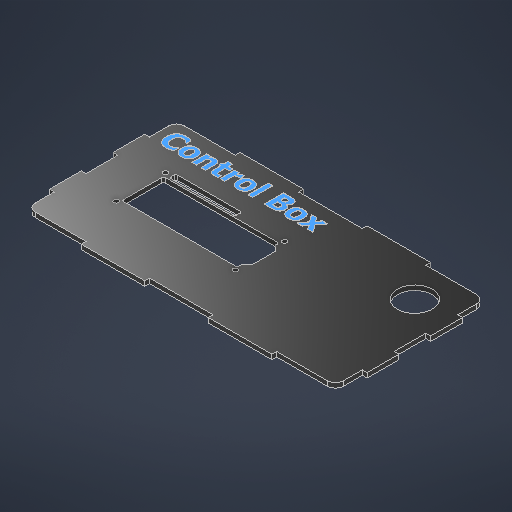
# Autodesk Inventor part: ControlBoxCeiling
Saved by Autodesk Inventor 2027.1 (Build 311270010, 270A)
## iProperties
Created: 2026-10-13
Part Number: ControlBoxCeiling
Material: MDF Medium Density Fiberboard
Document SubType Name: Modeling
Designer: SDS Scholar
Density: 0.8 g/cm^3
Appearance: Glossy - Black
Mass: 41.8002 g
Surface Area: 376.272 cm^2
Volume: 52.2502 cm^3
Author: SDS Scholar
Autodesk Inventor part; units mm, degrees
ref_plane "YZ Plane" through (0, 0, 0) normal (1, 0, 0) x (0, 1, 0)
ref_plane "XZ Plane" through (0, 0, 0) normal (0, 1, 0) x (-1, 0, 0)
ref_plane "XY Plane" through (0, 0, 0) normal (0, 0, 1) x (1, 0, 0)
sketch "Sketch1" plane through (0, 0, 0) normal (0, 1, 0) x (-1, 0, 0)
  line L0 (100, 50) -> (-100, 50)
  line L1 (-100, 50) -> (-100, -50)
  line L2 (-100, -50) -> (100, -50)
  line L3 (100, -50) -> (100, 50)
  line L4 (0, -50) -> (0, 81.8372) construction
  line L5 (0, 0) -> (100, 0) construction
  circle A0 centre (-75, -25) radius 11
  dimension "d0" = 100
  dimension "d1" = 200
  dimension "d21" = 22
  dimension "d22" = 25
  dimension "d23" = 25
  constraints: 12 end point, 2 midpoint, 2 parallel, 2 perpendicular, 1 centre point, 1 horizontal, 1 horizontal alignment, 1 vertical, 1 vertical alignment
  measures "d0" distance of L2.end L0.start
  measures "d1" distance of L1.end L2.end
  measures "d21" diameter of A0
  measures "d22" distance from line of L2 A0.centre
  measures "d23" distance from line of L1 A0.centre
extrude "Extrusion1" add sketch "Sketch1" along normal blind 3
sketch "Sketch2" plane through (0, 3, 0) normal (0, 1, 0) x (1, 0, 0)
  line L0 (100, -50) -> (100, 50) projected
  line L1 (100, 50) -> (-100, 50) projected
  line L2 (-100, 50) -> (-100, -50) projected
  line L3 (-100, -50) -> (100, -50) projected
  circle A0 centre (75, 25) radius 11 projected
  line L4 (-97, 47) -> (97, 47)
  line L5 (97, 47) -> (97, -47)
  line L6 (97, -47) -> (-97, -47)
  line L7 (-97, -47) -> (-97, 47)
  line L8 (-100, 50) -> (-60, 50)
  line L9 (-60, 50) -> (-60, 47)
  line L10 (-60, 47) -> (-100, 47)
  line L11 (-100, 47) -> (-100, 50)
  line L12 (-100, 0) -> (100, 0) construction
  line L13 (0, 50) -> (0, -50) construction
  line L14 (-20, 50) -> (-20, 47)
  line L15 (20, 50) -> (20, 47)
  line L16 (60, 50) -> (60, 47)
  line L17 (-60, -50) -> (-60, -47)
  line L18 (-20, -50) -> (-20, -47)
  line L19 (20, -50) -> (20, -47)
  line L20 (60, -50) -> (60, -47)
  line L21 (-100, 50) -> (-100, -50) projected
  line L22 (-100, 50) -> (-97, 50)
  line L23 (-97, 50) -> (-97, 30)
  line L24 (-97, 30) -> (-100, 30)
  line L25 (-100, 30) -> (-100, 50)
  line L26 (-97, 10) -> (-100, 10)
  line L27 (-97, -10) -> (-100, -10)
  line L28 (-97, -30) -> (-100, -30)
  line L29 (97, 30) -> (100, 30)
  line L30 (97, 10) -> (100, 10)
  line L31 (97, -10) -> (100, -10)
  line L32 (97, -30) -> (100, -30)
  dimension "d64" = 3
  dimension "d65" = 40
  dimension "d68" = 40
  dimension "d73" = 20
  dimension "d76" = 20
  constraints: 56 end point, 16 symmetric about line, 4 midpoint, 4 parallel, 3 horizontal, 2 perpendicular, 2 point on line, 1 vertical, 21 other
  measures "d64" distance between parallel lines of L1 L4
  measures "d65" distance of L9.end L10.end
  measures "d68" distance of L8.end L14.start
  measures "d73" distance of L22.end L23.end
  measures "d76" distance of L23.end L26.start
extrude "Extrusion2" cut sketch "Sketch2" against normal through all contours L3 L20 L6 L5 L32 L0 | L31 L5 L30 L0 | L3 L18 L6 L19 | L29 L5 L4 L16 L1 L0 | L3 L2 L28 L7 L6 L17 | L15 L4 L14 L1 | L2 L26 L7 L27 | L9 L4 L23 L1 | L2 L10 L7 L24 | L23 L10 L2 L1
sketch "Sketch3" plane through (0, 3, 0) normal (0, 1, 0) x (1, 0, 0)
  line L0 (-92.3688, 42.1211) -> (16.5966, 42.1211) construction
  line L1 (16.5966, 42.1211) -> (16.5966, 25.6389) construction
  line L2 (16.5966, 25.6389) -> (-92.3688, 25.6389) construction
  line L3 (-92.3688, 25.6389) -> (-92.3688, 42.1211) construction
  spline S0 degree 2 poles (-85.8437, 29.1401) (-88.5921, 29.1401) (-91.8152, 32.4619) (-91.8152, 35.4674) knots 0 0 0 1 2 2 2
  spline S1 degree 2 poles (-91.8152, 35.4674) (-91.8152, 38.3642) (-88.5823, 41.8146) (-85.8338, 41.8146) knots 0 0 0 1 2 2 2
  spline S2 degree 2 poles (-85.8338, 41.8146) (-85.1121, 41.8146) (-83.9455, 41.6465) (-83.4116, 41.5081) knots 0 0 0 1 2 2 2
  spline S3 degree 2 poles (-83.4116, 41.5081) (-82.9964, 41.3796) (-82.0176, 40.9545) (-81.7111, 40.7963) knots 0 0 0 1 2 2 2
  line L4 (-81.7111, 40.7963) -> (-81.7111, 37.8896)
  line L5 (-81.7111, 37.8896) -> (-82.0176, 37.8896)
  spline S4 degree 2 poles (-82.0176, 37.8896) (-82.245, 38.0874) (-82.9173, 38.641) (-83.3424, 38.8981) knots 0 0 0 1 2 2 2
  spline S5 degree 2 poles (-83.3424, 38.8981) (-83.7675, 39.165) (-84.7858, 39.5308) (-85.3494, 39.5308) knots 0 0 0 1 2 2 2
  spline S6 degree 2 poles (-85.3494, 39.5308) (-86.0118, 39.5308) (-87.1092, 39.1156) (-87.6134, 38.5916) knots 0 0 0 1 2 2 2
  spline S7 degree 2 poles (-87.6134, 38.5916) (-88.0682, 38.1269) (-88.6515, 36.5352) (-88.6515, 35.4576) knots 0 0 0 1 2 2 2
  spline S8 degree 2 poles (-88.6515, 35.4576) (-88.6515, 34.3206) (-88.0484, 32.7684) (-87.5541, 32.2939) knots 0 0 0 1 2 2 2
  spline S9 degree 2 poles (-87.5541, 32.2939) (-87.0795, 31.8292) (-85.9129, 31.4238) (-85.3296, 31.4238) knots 0 0 0 1 2 2 2
  spline S10 degree 2 poles (-85.3296, 31.4238) (-84.7265, 31.4238) (-83.6291, 31.8292) (-83.2534, 32.0764) knots 0 0 0 1 2 2 2
  spline S11 degree 2 poles (-83.2534, 32.0764) (-82.8382, 32.3235) (-82.2153, 32.8475) (-81.9879, 33.0551) knots 0 0 0 1 2 2 2
  line L6 (-81.9879, 33.0551) -> (-81.7111, 33.0551)
  line L7 (-81.7111, 33.0551) -> (-81.7111, 30.188)
  spline S12 degree 2 poles (-81.7111, 30.188) (-82.0473, 30.0298) (-82.9272, 29.6344) (-83.4017, 29.496) knots 0 0 0 1 2 2 2
  spline S13 degree 2 poles (-83.4017, 29.496) (-83.9751, 29.318) (-84.9737, 29.1401) (-85.8437, 29.1401) knots 0 0 0 1 2 2 2
  spline S14 degree 2 poles (-71.2413, 33.9746) (-71.2413, 31.7007) (-73.7228, 29.0906) (-75.9868, 29.0906) knots 0 0 0 1 2 2 2
  spline S15 degree 2 poles (-75.9868, 29.0906) (-78.2409, 29.0906) (-80.7422, 31.7007) (-80.7422, 33.9746) knots 0 0 0 1 2 2 2
  spline S16 degree 2 poles (-80.7422, 33.9746) (-80.7422, 36.2683) (-78.2409, 38.8684) (-75.9868, 38.8684) knots 0 0 0 1 2 2 2
  spline S17 degree 2 poles (-75.9868, 38.8684) (-73.7327, 38.8684) (-71.2413, 36.2584) (-71.2413, 33.9746) knots 0 0 0 1 2 2 2
  spline S18 degree 2 poles (-74.1776, 33.9548) (-74.1776, 34.7754) (-74.4445, 35.8728) (-74.6818, 36.199) knots 0 0 0 1 2 2 2
  spline S19 degree 2 poles (-74.6818, 36.199) (-74.9388, 36.5451) (-75.5815, 36.812) (-75.9868, 36.812) knots 0 0 0 1 2 2 2
  spline S20 degree 2 poles (-75.9868, 36.812) (-76.3823, 36.812) (-77.0051, 36.5747) (-77.2622, 36.2386) knots 0 0 0 1 2 2 2
  spline S21 degree 2 poles (-77.2622, 36.2386) (-77.5093, 35.9222) (-77.8059, 34.805) (-77.8059, 33.9548) knots 0 0 0 1 2 2 2
  spline S22 degree 2 poles (-77.8059, 33.9548) (-77.8059, 33.1144) (-77.5291, 32.0764) (-77.3017, 31.76) knots 0 0 0 1 2 2 2
  spline S23 degree 2 poles (-77.3017, 31.76) (-77.0743, 31.4436) (-76.3823, 31.147) (-75.967, 31.147) knots 0 0 0 1 2 2 2
  spline S24 degree 2 poles (-75.967, 31.147) (-75.621, 31.147) (-74.9092, 31.4436) (-74.6917, 31.7402) knots 0 0 0 1 2 2 2
  spline S25 degree 2 poles (-74.6917, 31.7402) (-74.4445, 32.0862) (-74.1776, 33.0848) (-74.1776, 33.9548) knots 0 0 0 1 2 2 2
  line L8 (-61.1075, 29.3773) -> (-63.9944, 29.3773)
  line L9 (-63.9944, 29.3773) -> (-63.9944, 33.935)
  spline S26 degree 2 poles (-63.9944, 33.935) (-63.9944, 34.4986) (-64.0834, 35.6059) (-64.202, 35.8629) knots 0 0 0 1 2 2 2
  spline S27 degree 2 poles (-64.202, 35.8629) (-64.3503, 36.1793) (-64.904, 36.4462) (-65.3785, 36.4462) knots 0 0 0 1 2 2 2
  spline S28 degree 2 poles (-65.3785, 36.4462) (-65.7246, 36.4462) (-66.4463, 36.1793) (-66.8516, 35.8926) knots 0 0 0 1 2 2 2
  line L10 (-66.8516, 35.8926) -> (-66.8516, 29.3773)
  line L11 (-66.8516, 29.3773) -> (-69.7187, 29.3773)
  line L12 (-69.7187, 29.3773) -> (-69.7187, 38.5817)
  line L13 (-69.7187, 38.5817) -> (-66.8516, 38.5817)
  line L14 (-66.8516, 38.5817) -> (-66.8516, 37.5634)
  spline S29 degree 2 poles (-66.8516, 37.5634) (-66.1497, 38.1566) (-64.815, 38.8289) (-64.0043, 38.8289) knots 0 0 0 1 2 2 2
  spline S30 degree 2 poles (-64.0043, 38.8289) (-62.6004, 38.8289) (-61.1075, 37.0493) (-61.1075, 35.3686) knots 0 0 0 1 2 2 2
  line L15 (-61.1075, 35.3686) -> (-61.1075, 29.3773)
  spline S31 degree 2 poles (-55.4623, 29.1994) (-57.2122, 29.1994) (-58.8139, 30.6428) (-58.8139, 32.284) knots 0 0 0 1 2 2 2
  line L16 (-58.8139, 32.284) -> (-58.8139, 36.5846)
  line L17 (-58.8139, 36.5846) -> (-59.9113, 36.5846)
  line L18 (-59.9113, 36.5846) -> (-59.9113, 38.5817)
  line L19 (-59.9113, 38.5817) -> (-58.8139, 38.5817)
  line L20 (-58.8139, 38.5817) -> (-58.8139, 41.2115)
  line L21 (-58.8139, 41.2115) -> (-55.9468, 41.2115)
  line L22 (-55.9468, 41.2115) -> (-55.9468, 38.5817)
  line L23 (-55.9468, 38.5817) -> (-53.1785, 38.5817)
  line L24 (-53.1785, 38.5817) -> (-53.1785, 36.5846)
  line L25 (-53.1785, 36.5846) -> (-55.9468, 36.5846)
  line L26 (-55.9468, 36.5846) -> (-55.9468, 33.3122)
  spline S32 degree 2 poles (-55.9468, 33.3122) (-55.9468, 32.8277) (-55.927, 32.106) (-55.8084, 31.8193) knots 0 0 0 1 2 2 2
  spline S33 degree 2 poles (-55.8084, 31.8193) (-55.6897, 31.5326) (-55.1064, 31.1965) (-54.5528, 31.1965) knots 0 0 0 1 2 2 2
  spline S34 degree 2 poles (-54.5528, 31.1965) (-54.3155, 31.1965) (-53.574, 31.3942) (-53.4257, 31.4733) knots 0 0 0 1 2 2 2
  line L27 (-53.4257, 31.4733) -> (-53.1785, 31.4733)
  line L28 (-53.1785, 31.4733) -> (-53.1785, 29.4564)
  spline S35 degree 2 poles (-53.1785, 29.4564) (-53.6432, 29.3378) (-54.6912, 29.1994) (-55.4623, 29.1994) knots 0 0 0 1 2 2 2
  line L29 (-45.8328, 35.8629) -> (-46.0701, 35.8629)
  spline S36 degree 2 poles (-46.0701, 35.8629) (-46.2382, 35.9222) (-46.861, 35.9815) (-47.2367, 35.9815) knots 0 0 0 1 2 2 2
  spline S37 degree 2 poles (-47.2367, 35.9815) (-47.6816, 35.9815) (-48.6802, 35.7146) (-49.1448, 35.5367) knots 0 0 0 1 2 2 2
  line L30 (-49.1448, 35.5367) -> (-49.1448, 29.3773)
  line L31 (-49.1448, 29.3773) -> (-52.0119, 29.3773)
  line L32 (-52.0119, 29.3773) -> (-52.0119, 38.5817)
  line L33 (-52.0119, 38.5817) -> (-49.1448, 38.5817)
  line L34 (-49.1448, 38.5817) -> (-49.1448, 37.2569)
  spline S38 degree 2 poles (-49.1448, 37.2569) (-48.9471, 37.4349) (-48.255, 37.9885) (-47.9683, 38.1566) knots 0 0 0 1 2 2 2
  spline S39 degree 2 poles (-47.9683, 38.1566) (-47.652, 38.3444) (-46.8215, 38.6114) (-46.4557, 38.6114) knots 0 0 0 1 2 2 2
  spline S40 degree 2 poles (-46.4557, 38.6114) (-46.3173, 38.6114) (-45.9712, 38.5916) (-45.8328, 38.5817) knots 0 0 0 1 2 2 2
  line L35 (-45.8328, 38.5817) -> (-45.8328, 35.8629)
  spline S41 degree 2 poles (-35.9067, 33.9746) (-35.9067, 31.7007) (-38.3883, 29.0906) (-40.6523, 29.0906) knots 0 0 0 1 2 2 2
  spline S42 degree 2 poles (-40.6523, 29.0906) (-42.9064, 29.0906) (-45.4077, 31.7007) (-45.4077, 33.9746) knots 0 0 0 1 2 2 2
  spline S43 degree 2 poles (-45.4077, 33.9746) (-45.4077, 36.2683) (-42.9064, 38.8684) (-40.6523, 38.8684) knots 0 0 0 1 2 2 2
  spline S44 degree 2 poles (-40.6523, 38.8684) (-38.3981, 38.8684) (-35.9067, 36.2584) (-35.9067, 33.9746) knots 0 0 0 1 2 2 2
  spline S45 degree 2 poles (-38.843, 33.9548) (-38.843, 34.7754) (-39.11, 35.8728) (-39.3473, 36.199) knots 0 0 0 1 2 2 2
  spline S46 degree 2 poles (-39.3473, 36.199) (-39.6043, 36.5451) (-40.2469, 36.812) (-40.6523, 36.812) knots 0 0 0 1 2 2 2
  spline S47 degree 2 poles (-40.6523, 36.812) (-41.0477, 36.812) (-41.6706, 36.5747) (-41.9276, 36.2386) knots 0 0 0 1 2 2 2
  spline S48 degree 2 poles (-41.9276, 36.2386) (-42.1748, 35.9222) (-42.4714, 34.805) (-42.4714, 33.9548) knots 0 0 0 1 2 2 2
  spline S49 degree 2 poles (-42.4714, 33.9548) (-42.4714, 33.1144) (-42.1946, 32.0764) (-41.9672, 31.76) knots 0 0 0 1 2 2 2
  spline S50 degree 2 poles (-41.9672, 31.76) (-41.7398, 31.4436) (-41.0477, 31.147) (-40.6325, 31.147) knots 0 0 0 1 2 2 2
  spline S51 degree 2 poles (-40.6325, 31.147) (-40.2865, 31.147) (-39.5746, 31.4436) (-39.3571, 31.7402) knots 0 0 0 1 2 2 2
  spline S52 degree 2 poles (-39.3571, 31.7402) (-39.11, 32.0862) (-38.843, 33.0848) (-38.843, 33.9548) knots 0 0 0 1 2 2 2
  line L36 (-31.5171, 29.3773) -> (-34.3842, 29.3773)
  line L37 (-34.3842, 29.3773) -> (-34.3842, 42.1211)
  line L38 (-34.3842, 42.1211) -> (-31.5171, 42.1211)
  line L39 (-31.5171, 42.1211) -> (-31.5171, 29.3773)
  spline S53 degree 2 poles (-14.4925, 33.1144) (-14.4925, 32.2049) (-15.1845, 30.8307) (-15.7579, 30.3759) knots 0 0 0 1 2 2 2
  spline S54 degree 2 poles (-15.7579, 30.3759) (-16.45, 29.8321) (-18.0912, 29.3773) (-19.3665, 29.3773) knots 0 0 0 1 2 2 2
  line L40 (-19.3665, 29.3773) -> (-24.2406, 29.3773)
  line L41 (-24.2406, 29.3773) -> (-24.2406, 41.5773)
  line L42 (-24.2406, 41.5773) -> (-19.94, 41.5773)
  spline S55 degree 2 poles (-19.94, 41.5773) (-18.5954, 41.5773) (-17.2113, 41.3697) (-16.6082, 41.0435) knots 0 0 0 1 2 2 2
  spline S56 degree 2 poles (-16.6082, 41.0435) (-15.9458, 40.6974) (-15.3032, 39.511) (-15.3032, 38.7399) knots 0 0 0 1 2 2 2
  spline S57 degree 2 poles (-15.3032, 38.7399) (-15.3032, 37.8501) (-16.193, 36.4561) (-16.9839, 36.1298) knots 0 0 0 1 2 2 2
  line L43 (-16.9839, 36.1298) -> (-16.9839, 36.0705)
  spline S58 degree 2 poles (-16.9839, 36.0705) (-15.8469, 35.8332) (-14.4925, 34.3602) (-14.4925, 33.1144) knots 0 0 0 1 2 2 2
  spline S59 degree 2 poles (-17.6562, 33.1639) (-17.6562, 33.7373) (-18.1109, 34.3799) (-18.5657, 34.548) knots 0 0 0 1 2 2 2
  spline S60 degree 2 poles (-18.5657, 34.548) (-18.8426, 34.6567) (-19.8213, 34.6765) (-20.632, 34.6765) knots 0 0 0 1 2 2 2
  line L44 (-20.632, 34.6765) -> (-21.1955, 34.6765)
  line L45 (-21.1955, 34.6765) -> (-21.1955, 31.6018)
  line L46 (-21.1955, 31.6018) -> (-21.0275, 31.6018)
  spline S61 degree 2 poles (-21.0275, 31.6018) (-19.8411, 31.6018) (-18.9315, 31.6315) (-18.457, 31.8391) knots 0 0 0 1 2 2 2
  spline S62 degree 2 poles (-18.457, 31.8391) (-18.0417, 32.0269) (-17.6562, 32.719) (-17.6562, 33.1639) knots 0 0 0 1 2 2 2
  spline S63 degree 2 poles (-18.4174, 38.1368) (-18.4174, 38.4334) (-18.7239, 39.0563) (-19.0403, 39.1947) knots 0 0 0 1 2 2 2
  spline S64 degree 2 poles (-19.0403, 39.1947) (-19.3369, 39.3331) (-20.1673, 39.3529) (-20.9879, 39.3529) knots 0 0 0 1 2 2 2
  line L47 (-20.9879, 39.3529) -> (-21.1955, 39.3529)
  line L48 (-21.1955, 39.3529) -> (-21.1955, 36.7626)
  line L49 (-21.1955, 36.7626) -> (-20.81, 36.7626)
  spline S65 degree 2 poles (-20.81, 36.7626) (-20.0289, 36.7626) (-19.3962, 36.7922) (-19.0601, 36.9504) knots 0 0 0 1 2 2 2
  spline S66 degree 2 poles (-19.0601, 36.9504) (-18.6943, 37.1284) (-18.4174, 37.7315) (-18.4174, 38.1368) knots 0 0 0 1 2 2 2
  spline S67 degree 2 poles (-4.072, 33.9746) (-4.072, 31.7007) (-6.5536, 29.0906) (-8.8176, 29.0906) knots 0 0 0 1 2 2 2
  spline S68 degree 2 poles (-8.8176, 29.0906) (-11.0717, 29.0906) (-13.573, 31.7007) (-13.573, 33.9746) knots 0 0 0 1 2 2 2
  spline S69 degree 2 poles (-13.573, 33.9746) (-13.573, 36.2683) (-11.0717, 38.8684) (-8.8176, 38.8684) knots 0 0 0 1 2 2 2
  spline S70 degree 2 poles (-8.8176, 38.8684) (-6.5635, 38.8684) (-4.072, 36.2584) (-4.072, 33.9746) knots 0 0 0 1 2 2 2
  spline S71 degree 2 poles (-7.0084, 33.9548) (-7.0084, 34.7754) (-7.2753, 35.8728) (-7.5126, 36.199) knots 0 0 0 1 2 2 2
  spline S72 degree 2 poles (-7.5126, 36.199) (-7.7696, 36.5451) (-8.4122, 36.812) (-8.8176, 36.812) knots 0 0 0 1 2 2 2
  spline S73 degree 2 poles (-8.8176, 36.812) (-9.2131, 36.812) (-9.8359, 36.5747) (-10.093, 36.2386) knots 0 0 0 1 2 2 2
  spline S74 degree 2 poles (-10.093, 36.2386) (-10.3401, 35.9222) (-10.6367, 34.805) (-10.6367, 33.9548) knots 0 0 0 1 2 2 2
  spline S75 degree 2 poles (-10.6367, 33.9548) (-10.6367, 33.1144) (-10.3599, 32.0764) (-10.1325, 31.76) knots 0 0 0 1 2 2 2
  spline S76 degree 2 poles (-10.1325, 31.76) (-9.9051, 31.4436) (-9.2131, 31.147) (-8.7978, 31.147) knots 0 0 0 1 2 2 2
  spline S77 degree 2 poles (-8.7978, 31.147) (-8.4518, 31.147) (-7.74, 31.4436) (-7.5225, 31.7402) knots 0 0 0 1 2 2 2
  spline S78 degree 2 poles (-7.5225, 31.7402) (-7.2753, 32.0862) (-7.0084, 33.0848) (-7.0084, 33.9548) knots 0 0 0 1 2 2 2
  line L50 (6.5263, 29.3773) -> (3.1649, 29.3773)
  line L51 (3.1649, 29.3773) -> (1.415, 32.017)
  line L52 (1.415, 32.017) -> (-0.3844, 29.3773)
  line L53 (-0.3844, 29.3773) -> (-3.6766, 29.3773)
  line L54 (-3.6766, 29.3773) -> (-0.2855, 33.9845)
  line L55 (-0.2855, 33.9845) -> (-3.6173, 38.5817)
  line L56 (-3.6173, 38.5817) -> (-0.2558, 38.5817)
  line L57 (-0.2558, 38.5817) -> (1.4644, 35.9914)
  line L58 (1.4644, 35.9914) -> (3.1946, 38.5817)
  line L59 (3.1946, 38.5817) -> (6.4868, 38.5817)
  line L60 (6.4868, 38.5817) -> (3.155, 34.0537)
  line L61 (3.155, 34.0537) -> (6.5263, 29.3773)
  point P0 (0, 0)
  constraints: 2 other
emboss "Emboss1" sketch "Sketch3" operation add depth 0.1 direction (0, -1, 0)
fillet "Fillet1" radius 5 4 edges at (97, 1.5, 47) (97, 1.5, -47) (-97, 1.5, 47) (-97, 1.5, -47)
sketch "Sketch4" plane through (0, 3, 0) normal (0, 1, 0) x (1, 0, 0)
  line L0 (1.4644, 35.9914) -> (3.1946, 38.5817) projected
  line L1 (3.1946, 38.5817) -> (6.4868, 38.5817) projected
  line L2 (6.4868, 38.5817) -> (3.155, 34.0537) projected
  line L3 (3.155, 34.0537) -> (6.5263, 29.3773) projected
  line L4 (6.5263, 29.3773) -> (3.1649, 29.3773) projected
  line L5 (3.1649, 29.3773) -> (1.415, 32.017) projected
  line L6 (1.415, 32.017) -> (-0.3844, 29.3773) projected
  line L7 (-0.3844, 29.3773) -> (-3.6766, 29.3773) projected
  line L8 (-3.6766, 29.3773) -> (-0.2855, 33.9845) projected
  line L9 (-0.2855, 33.9845) -> (-3.6173, 38.5817) projected
  line L10 (-3.6173, 38.5817) -> (-0.2558, 38.5817) projected
  line L11 (-0.2558, 38.5817) -> (1.4644, 35.9914) projected
  line L12 (-81.9879, 33.0551) -> (-81.7111, 33.0551) projected
  line L13 (-81.7111, 33.0551) -> (-81.7111, 30.188) projected
  line L14 (-81.7111, 40.7963) -> (-81.7111, 37.8896) projected
  line L15 (-81.7111, 37.8896) -> (-82.0176, 37.8896) projected
  line L16 (-55.9468, 36.5846) -> (-55.9468, 33.3122) projected
  line L17 (-53.4257, 31.4733) -> (-53.1785, 31.4733) projected
  line L18 (-53.1785, 31.4733) -> (-53.1785, 29.4564) projected
  line L19 (-58.8139, 32.284) -> (-58.8139, 36.5846) projected
  line L20 (-58.8139, 36.5846) -> (-59.9113, 36.5846) projected
  line L21 (-59.9113, 36.5846) -> (-59.9113, 38.5817) projected
  line L22 (-59.9113, 38.5817) -> (-58.8139, 38.5817) projected
  line L23 (-58.8139, 38.5817) -> (-58.8139, 41.2115) projected
  line L24 (-58.8139, 41.2115) -> (-55.9468, 41.2115) projected
  line L25 (-55.9468, 41.2115) -> (-55.9468, 38.5817) projected
  line L26 (-55.9468, 38.5817) -> (-53.1785, 38.5817) projected
  line L27 (-53.1785, 38.5817) -> (-53.1785, 36.5846) projected
  line L28 (-53.1785, 36.5846) -> (-55.9468, 36.5846) projected
  line L29 (-69.7187, 29.3773) -> (-69.7187, 38.5817) projected
  line L30 (-69.7187, 38.5817) -> (-66.8516, 38.5817) projected
  line L31 (-66.8516, 38.5817) -> (-66.8516, 37.5634) projected
  line L32 (-61.1075, 35.3686) -> (-61.1075, 29.3773) projected
  line L33 (-61.1075, 29.3773) -> (-63.9944, 29.3773) projected
  line L34 (-63.9944, 29.3773) -> (-63.9944, 33.935) projected
  line L35 (-66.8516, 35.8926) -> (-66.8516, 29.3773) projected
  line L36 (-66.8516, 29.3773) -> (-69.7187, 29.3773) projected
  line L37 (-31.5171, 29.3773) -> (-34.3842, 29.3773) projected
  line L38 (-34.3842, 29.3773) -> (-34.3842, 42.1211) projected
  line L39 (-34.3842, 42.1211) -> (-31.5171, 42.1211) projected
  line L40 (-31.5171, 42.1211) -> (-31.5171, 29.3773) projected
  line L41 (-49.1448, 38.5817) -> (-49.1448, 37.2569) projected
  line L42 (-45.8328, 38.5817) -> (-45.8328, 35.8629) projected
  line L43 (-45.8328, 35.8629) -> (-46.0701, 35.8629) projected
  line L44 (-49.1448, 35.5367) -> (-49.1448, 29.3773) projected
  line L45 (-49.1448, 29.3773) -> (-52.0119, 29.3773) projected
  line L46 (-52.0119, 29.3773) -> (-52.0119, 38.5817) projected
  line L47 (-52.0119, 38.5817) -> (-49.1448, 38.5817) projected
  line L48 (-16.9839, 36.1298) -> (-16.9839, 36.0705) projected
  line L49 (-19.3665, 29.3773) -> (-24.2406, 29.3773) projected
  line L50 (-24.2406, 29.3773) -> (-24.2406, 41.5773) projected
  line L51 (-24.2406, 41.5773) -> (-19.94, 41.5773) projected
  arc A0 (-92, 47) -> (-97, 42) centre (-92, 42) ccw projected
  line L52 (-97, 42) -> (-97, 30) projected
  line L53 (-97, 30) -> (-100, 30) projected
  line L54 (-100, 30) -> (-100, 10) projected
  line L55 (-100, 10) -> (-97, 10) projected
  line L56 (-97, 10) -> (-97, -10) projected
  line L57 (-97, -10) -> (-100, -10) projected
  line L58 (-100, -10) -> (-100, -30) projected
  line L59 (-100, -30) -> (-97, -30) projected
  line L60 (-97, -30) -> (-97, -42) projected
  arc A1 (-97, -42) -> (-92, -47) centre (-92, -42) ccw projected
  line L61 (-92, -47) -> (-60, -47) projected
  line L62 (-60, -47) -> (-60, -50) projected
  line L63 (-60, -50) -> (-20, -50) projected
  line L64 (-20, -50) -> (-20, -47) projected
  line L65 (-20, -47) -> (20, -47) projected
  line L66 (20, -47) -> (20, -50) projected
  line L67 (20, -50) -> (60, -50) projected
  line L68 (60, -50) -> (60, -47) projected
  line L69 (60, -47) -> (92, -47) projected
  arc A2 (92, -47) -> (97, -42) centre (92, -42) ccw projected
  line L70 (97, -42) -> (97, -30) projected
  line L71 (97, -30) -> (100, -30) projected
  line L72 (100, -30) -> (100, -10) projected
  line L73 (100, -10) -> (97, -10) projected
  line L74 (97, -10) -> (97, 10) projected
  line L75 (97, 10) -> (100, 10) projected
  line L76 (100, 10) -> (100, 30) projected
  line L77 (100, 30) -> (97, 30) projected
  line L78 (97, 30) -> (97, 42) projected
  arc A3 (97, 42) -> (92, 47) centre (92, 42) ccw projected
  line L79 (92, 47) -> (60, 47) projected
  line L80 (60, 47) -> (60, 50) projected
  line L81 (60, 50) -> (20, 50) projected
  line L82 (20, 50) -> (20, 47) projected
  line L83 (20, 47) -> (-20, 47) projected
  line L84 (-20, 47) -> (-20, 50) projected
  line L85 (-20, 50) -> (-60, 50) projected
  line L86 (-60, 50) -> (-60, 47) projected
  line L87 (-60, 47) -> (-92, 47) projected
  circle A4 centre (75, 25) radius 11 projected
  line L88 (-75, 18) -> (5, 18)
  line L89 (5, 18) -> (5, -18)
  line L90 (5, -18) -> (-75, -18)
  line L91 (-75, -18) -> (-75, 18)
  line L92 (-75, 0) -> (5, 0) construction
  line L93 (-35, 18) -> (-35, -18) construction
  circle A5 centre (-72.5, 15.5) radius 1.5
  circle A6 centre (-72.5, -15.5) radius 1.5
  circle A7 centre (2.5, 15.5) radius 1.5
  circle A8 centre (2.5, -15.5) radius 1.5
  line L94 (-67.5, 18) -> (-28, 18)
  line L95 (-27, 17) -> (-27, 15)
  line L96 (-28, 14) -> (-67.5, 14)
  line L97 (-68.5, 15) -> (-68.5, 17)
  arc A9 (-68.5, 15) -> (-67.5, 14) centre (-67.5, 15) ccw
  arc A10 (-28, 14) -> (-27, 15) centre (-28, 15) ccw
  arc A11 (-27, 17) -> (-28, 18) centre (-28, 17) ccw
  arc A12 (-67.5, 18) -> (-68.5, 17) centre (-67.5, 17) ccw
  line L98 (-70, 12.8) -> (0.5, 12.8)
  line L99 (1.5, 11.8) -> (1.5, -12.4)
  line L100 (0.5, -13.4) -> (-70, -13.4)
  line L101 (-71, -12.4) -> (-71, 11.8)
  arc A13 (-70, 12.8) -> (-71, 11.8) centre (-70, 11.8) ccw
  arc A14 (-71, -12.4) -> (-70, -13.4) centre (-70, -12.4) ccw
  arc A15 (0.5, -13.4) -> (1.5, -12.4) centre (0.5, -12.4) ccw
  arc A16 (1.5, 11.8) -> (0.5, 12.8) centre (0.5, 11.8) ccw
  line L102 (5, 7.5) -> (1.5, 11)
  line L103 (5, -7.5) -> (1.5, -11)
  line L104 (3.25, 9.25) -> (3.25, -9.25) construction
  point P0 (0, 0)
  point P1 (-68.5, 18)
  point P2 (-27, 14)
  point P3 (-27, 18)
  point P4 (-68.5, 14)
  point P5 (-12, 18)
  point P6 (-53.4365, 16.5)
  point P7 (-12.0635, 16.5)
  point P8 (1.5, -13.4)
  point P9 (1.5, 12.8)
  point P10 (-71, -13.4)
  point P11 (3.25, 0)
  dimension "d82" = 80
  dimension "d83" = 36
  dimension "d84" = 5
  dimension "d85" = 3
  dimension "d86" = 2.5
  dimension "d87" = 2.5
  dimension "d88" = 41.5
  dimension "d89" = 4
  dimension "d90" = 6.5
  dimension "d93" = 1
  dimension "d94" = 72.5
  dimension "d95" = 26.2
  dimension "d96" = 4
  dimension "d97" = 5.2
  dimension "d98" = 1
  dimension "d104" = 45
  dimension "d105" = 45
  dimension "d107" = 15
  constraints: 34 end point, 19 point on line, 16 point on circle, 16 tangent, 12 centre point, 7 midpoint, 6 equal radius, 6 parallel, 4 horizontal, 3 perpendicular, 3 symmetric about line, 2 horizontal alignment, 50 other
  measures "d82" distance of L89.end L90.end
  measures "d83" distance of L88.end L89.end
  measures "d84" distance from line of point (0, 0) L89
  measures "d85" diameter of A5
  measures "d86" distance from line of L91 A5.centre
  measures "d87" distance from line of L88 A5.centre
  measures "d88" distance of point (-27, 14) point (-68.5, 14)
  measures "d89" distance of point (-27, 18) point (-27, 14)
  measures "d90" distance between parallel lines of L91 L97
  measures "d93" radius of A9
  measures "d94" distance of point (1.5, -13.4) point (-71, -13.4)
  measures "d95" distance of point (1.5, 12.8) point (1.5, -13.4)
  measures "d96" distance between parallel lines of L91 L101
  measures "d97" distance between parallel lines of L88 L98
  measures "d98" radius of A13
  measures "d104" angle of L89 L102
  measures "d105" angle of L89 L103
  measures "d107" distance of L103.start L102.start
extrude "Extrusion3" cut sketch "Sketch4" against normal through all contours L88 A11 L95 A10 L96 A9 L97 A12 | L103 L99 L102 L89 | L99 A15 L100 A14 L101 A13 L98 A16 | A5 | A6 | A7 | A8
equation "\"d0\" = ContolBoxLength"
equation "\"d1\" = ContolBoxWidth"
equation "\"GridProcutClearance\" = 5"
equation "\"GridBorderThickness\" = 5"
equation "\"GridBorderFillets\" = 7"
equation "\"GridTotalSize\" = 65"
equation "\"GridRobotClearance\" = 65"
equation "\"AluminiumExtrusionClearance\" = 35"
equation "\"BaseTotalLength\" = 885"
equation "\"WorkspaceLength\" = 515"
equation "\"WorkspaceHeight\" = 183"
equation "\"AxesBaseFillet\" = 15"
equation "\"Zaxis\" = 197"
equation "\"ProductTotalHeight\" = 45"
equation "\"VerticalStroke\" = 105"
equation "\"BackArea\" = 165"
equation "\"CylinderStroke\" = 75"
equation "\"BoxesWidth\" = 125"
equation "\"ContolBoxLength\" = 100"
equation "\"ContolBoxWidth\" = 200"
equation "\"BaseWoodThickness\" = 7"
equation "\"kerf\" = 1.5"
equation "\"Kerf\" = 0.3"
equation "\"RxThickness\" = 1.8"
equation "\"support_2\" = 265"
body "Solid1"
